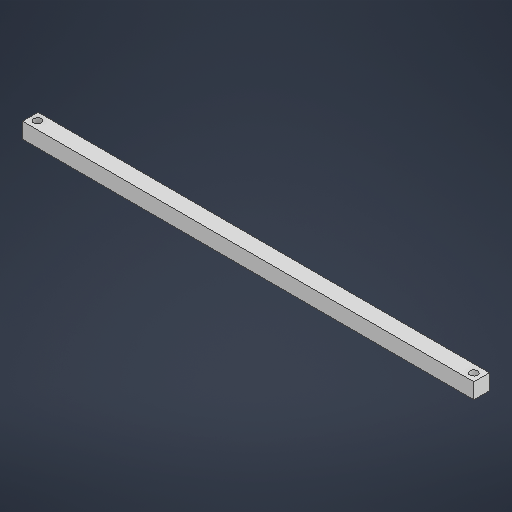
# Autodesk Inventor part: forearm
Saved by Autodesk Inventor 2027 (Build 310192000, 192)
## iProperties
Created: 2026-11-19
Part Number: forearm
Material: Generic
Document SubType Name: Modeling
Designer: lukeg
Density: 1 g/cm^3
Appearance: Default
Author: lukeg
Autodesk Inventor part; units mm, degrees
ref_plane "YZ Plane" through (0, 0, 0) normal (1, 0, 0) x (0, 1, 0)
ref_plane "XZ Plane" through (0, 0, 0) normal (0, 1, 0) x (-1, 0, 0)
ref_plane "XY Plane" through (0, 0, 0) normal (0, 0, 1) x (1, 0, 0)
sketch "Sketch1" plane through (0, 0, 0) normal (0, 1, 0) x (-1, 0, 0)
  line L0 (0, 0) -> (-736.6, 0)
  line L1 (-736.6, 0) -> (-736.6, -25.4)
  line L2 (-736.6, -25.4) -> (0, -25.4)
  line L3 (0, -25.4) -> (0, 0)
  dimension "d0" = 736.6
  dimension "d1" = 25.4
  constraints: 8 end point, 2 parallel, 1 horizontal, 1 perpendicular
  measures "d0" distance of L2.end L1.end
  measures "d1" distance of L1.end L0.end
extrude "Extrusion1" add sketch "Sketch1" along normal blind 25.4
sketch "Sketch2" plane through (0, 25.4, 0) normal (0, 1, 0) x (1, 0, 0)
  point P0 (0, 0)
  point P1 (11.5945, 12.7824)
hole "Hole1" at (11.5945, 25.4, -12.7824) direction (0, -1, 0) diameter 12.7 end through all
sketch "Sketch3" plane through (0, 25.4, 0) normal (0, 1, 0) x (1, 0, 0)
  point P0 (0, 0)
  point P1 (724.0324, 12.4362)
hole "Hole2" at (724.0324, 25.4, -12.4362) direction (0, -1, 0) diameter 12.7 end through all
body "Solid1"
